Autodesk Fusion 360 part; units mm, degrees
(part 2 of 2)
sketch "Sketch127" plane through (-0.4, 0, 0) normal (1, 0, 0) x (0, 0, -1)
  line L0 (-20.3909, 26) -> (20.3909, 26)
  line L1 (20.3909, 26) -> (20.3909, 30.9997)
  line L2 (20.3909, 30.9997) -> (-20.3909, 30.9997)
  line L3 (-20.3909, 30.9997) -> (-20.3909, 26)
ref_plane "WorkPlane128" through (30.4, 0, 0) normal (1, 0, 0) x (0, 1, 0)
sketch "Sketch128" plane through (30.4, 0, 0) normal (1, 0, 0) x (0, 0, -1)
  line L0 (-20.5, 26) -> (20.5, 26)
  line L1 (20.5, 26) -> (20.5, 31)
  line L2 (20.5, 31) -> (-20.5, 31)
  line L3 (-20.5, 31) -> (-20.5, 26)
loft "Loft61" add profiles "Sketch127", "Sketch128" section 1 section 2 separate body makes body 67
ref_plane "WorkPlane129" through (29.6, 0, 0) normal (1, 0, 0) x (0, 1, 0)
sketch "Sketch129" plane through (29.6, 0, 0) normal (1, 0, 0) x (0, 0, -1)
  line L0 (-20.5, 26) -> (20.5, 26)
  line L1 (20.5, 26) -> (20.5, 31)
  line L2 (20.5, 31) -> (-20.5, 31)
  line L3 (-20.5, 31) -> (-20.5, 26)
ref_plane "WorkPlane130" through (60.4, 0, 0) normal (1, 0, 0) x (0, 1, 0)
sketch "Sketch130" plane through (60.4, 0, 0) normal (1, 0, 0) x (0, 0, -1)
  line L0 (-20.5, 26) -> (20.5, 26)
  line L1 (20.5, 26) -> (20.5, 31)
  line L2 (20.5, 31) -> (-20.5, 31)
  line L3 (-20.5, 31) -> (-20.5, 26)
loft "Loft62" add profiles "Sketch129", "Sketch130" section 1 section 2 separate body makes body 68
ref_plane "WorkPlane131" through (59.6, 0, 0) normal (1, 0, 0) x (0, 1, 0)
sketch "Sketch131" plane through (59.6, 0, 0) normal (1, 0, 0) x (0, 0, -1)
  line L0 (-20.5, 26) -> (20.5, 26)
  line L1 (20.5, 26) -> (20.5, 31)
  line L2 (20.5, 31) -> (-20.5, 31)
  line L3 (-20.5, 31) -> (-20.5, 26)
ref_plane "WorkPlane132" through (90.4, 0, 0) normal (1, 0, 0) x (0, 1, 0)
sketch "Sketch132" plane through (90.4, 0, 0) normal (1, 0, 0) x (0, 0, -1)
  line L0 (-20.5, 26) -> (20.5, 26)
  line L1 (20.5, 26) -> (20.5, 31)
  line L2 (20.5, 31) -> (-20.5, 31)
  line L3 (-20.5, 31) -> (-20.5, 26)
loft "Loft63" add profiles "Sketch131", "Sketch132" section 1 section 2 separate body makes body 69
ref_plane "WorkPlane133" through (89.6, 0, 0) normal (1, 0, 0) x (0, 1, 0)
sketch "Sketch133" plane through (89.6, 0, 0) normal (1, 0, 0) x (0, 0, -1)
  line L0 (-20.5, 26) -> (20.5, 26)
  line L1 (20.5, 26) -> (20.5, 31)
  line L2 (20.5, 31) -> (-20.5, 31)
  line L3 (-20.5, 31) -> (-20.5, 26)
ref_plane "WorkPlane134" through (120.4, 0, 0) normal (1, 0, 0) x (0, 1, 0)
sketch "Sketch134" plane through (120.4, 0, 0) normal (1, 0, 0) x (0, 0, -1)
  line L0 (-20.5, 26) -> (20.5, 26)
  line L1 (20.5, 26) -> (20.5, 30.9848)
  line L2 (20.5, 30.9848) -> (-20.5, 30.9848)
  line L3 (-20.5, 30.9848) -> (-20.5, 26)
loft "Loft64" add profiles "Sketch133", "Sketch134" section 1 section 2 separate body makes body 70
ref_plane "WorkPlane135" through (119.6, 0, 0) normal (1, 0, 0) x (0, 1, 0)
sketch "Sketch135" plane through (119.6, 0, 0) normal (1, 0, 0) x (0, 0, -1)
  line L0 (-20.5, 26) -> (20.5, 26)
  line L1 (20.5, 26) -> (20.5, 31)
  line L2 (20.5, 31) -> (-20.5, 31)
  line L3 (-20.5, 31) -> (-20.5, 26)
ref_plane "WorkPlane136" through (122.4, 0, 0) normal (1, 0, 0) x (0, 1, 0)
sketch "Sketch136" plane through (122.4, 0, 0) normal (1, 0, 0) x (0, 0, -1)
  line L0 (-20.4147, 25.9059) -> (20.4147, 25.9059)
  line L1 (20.4147, 25.9059) -> (20.4147, 30.8142)
  line L2 (20.4147, 30.8142) -> (-20.4147, 30.8142)
  line L3 (-20.4147, 30.8142) -> (-20.4147, 25.9059)
loft "Loft65" add profiles "Sketch135", "Sketch136" section 1 section 2 separate body makes body 71
ref_plane "WorkPlane137" through (121.6, 0, 0) normal (1, 0, 0) x (0, 1, 0)
sketch "Sketch137" plane through (121.6, 0, 0) normal (1, 0, 0) x (0, 0, -1)
  line L0 (-20.5, 26) -> (20.5, 26)
  line L1 (20.5, 26) -> (20.5, 30.939)
  line L2 (20.5, 30.939) -> (-20.5, 30.939)
  line L3 (-20.5, 30.939) -> (-20.5, 26)
ref_plane "WorkPlane138" through (132.0667, 0, 0) normal (1, 0, 0) x (0, 1, 0)
sketch "Sketch138" plane through (132.0667, 0, 0) normal (1, 0, 0) x (0, 0, -1)
  line L0 (-18.3534, 23.6314) -> (18.3534, 23.6314)
  line L1 (18.3534, 23.6314) -> (18.3534, 28.16)
  line L2 (18.3534, 28.16) -> (-18.3534, 28.16)
  line L3 (-18.3534, 28.16) -> (-18.3534, 23.6314)
loft "Loft66" add profiles "Sketch137", "Sketch138" section 1 section 2 separate body makes body 72
ref_plane "WorkPlane139" through (131.2667, 0, 0) normal (1, 0, 0) x (0, 1, 0)
sketch "Sketch139" plane through (131.2667, 0, 0) normal (1, 0, 0) x (0, 0, -1)
  line L0 (-18.524, 23.8196) -> (18.524, 23.8196)
  line L1 (18.524, 23.8196) -> (18.524, 28.3803)
  line L2 (18.524, 28.3803) -> (-18.524, 28.3803)
  line L3 (-18.524, 28.3803) -> (-18.524, 23.8196)
ref_plane "WorkPlane140" through (143.7333, 0, 0) normal (1, 0, 0) x (0, 1, 0)
sketch "Sketch140" plane through (143.7333, 0, 0) normal (1, 0, 0) x (0, 0, -1)
  line L0 (-15.8657, 20.8863) -> (15.8657, 20.8863)
  line L1 (15.8657, 20.8863) -> (15.8657, 24.9301)
  line L2 (15.8657, 24.9301) -> (-15.8657, 24.9301)
  line L3 (-15.8657, 24.9301) -> (-15.8657, 20.8863)
loft "Loft67" add profiles "Sketch139", "Sketch140" section 1 section 2 separate body makes body 73
ref_plane "WorkPlane141" through (142.9333, 0, 0) normal (1, 0, 0) x (0, 1, 0)
sketch "Sketch141" plane through (142.9333, 0, 0) normal (1, 0, 0) x (0, 0, -1)
  line L0 (-16.0363, 21.0745) -> (16.0363, 21.0745)
  line L1 (16.0363, 21.0745) -> (16.0363, 25.1527)
  line L2 (16.0363, 25.1527) -> (-16.0363, 25.1527)
  line L3 (-16.0363, 25.1527) -> (-16.0363, 21.0745)
ref_plane "WorkPlane142" through (155.4, 0, 0) normal (1, 0, 0) x (0, 1, 0)
sketch "Sketch142" plane through (155.4, 0, 0) normal (1, 0, 0) x (0, 0, -1)
  line L0 (-13.3779, 18.1412) -> (13.3779, 18.1412)
  line L1 (13.3779, 18.1412) -> (13.3779, 21.6616)
  line L2 (13.3779, 21.6616) -> (-13.3779, 21.6616)
  line L3 (-13.3779, 21.6616) -> (-13.3779, 18.1412)
loft "Loft68" add profiles "Sketch141", "Sketch142" section 1 section 2 separate body makes body 74
ref_plane "WorkPlane143" through (154.6, 0, 0) normal (1, 0, 0) x (0, 1, 0)
sketch "Sketch143" plane through (154.6, 0, 0) normal (1, 0, 0) x (0, 0, -1)
  line L0 (-13.5485, 18.3294) -> (13.5485, 18.3294)
  line L1 (13.5485, 18.3294) -> (13.5485, 21.8873)
  line L2 (13.5485, 21.8873) -> (-13.5485, 21.8873)
  line L3 (-13.5485, 21.8873) -> (-13.5485, 18.3294)
ref_plane "WorkPlane144" through (167.0667, 0, 0) normal (1, 0, 0) x (0, 1, 0)
sketch "Sketch144" plane through (167.0667, 0, 0) normal (1, 0, 0) x (0, 0, -1)
  line L0 (-10.8902, 15.3961) -> (10.8902, 15.3961)
  line L1 (10.8902, 15.3961) -> (10.8902, 18.336)
  line L2 (10.8902, 18.336) -> (-10.8902, 18.336)
  line L3 (-10.8902, 18.336) -> (-10.8902, 15.3961)
loft "Loft69" add profiles "Sketch143", "Sketch144" section 1 section 2 separate body makes body 75
ref_plane "WorkPlane145" through (166.2667, 0, 0) normal (1, 0, 0) x (0, 1, 0)
sketch "Sketch145" plane through (166.2667, 0, 0) normal (1, 0, 0) x (0, 0, -1)
  line L0 (-11.0608, 15.5843) -> (11.0608, 15.5843)
  line L1 (11.0608, 15.5843) -> (11.0608, 18.5666)
  line L2 (11.0608, 18.5666) -> (-11.0608, 18.5666)
  line L3 (-11.0608, 18.5666) -> (-11.0608, 15.5843)
ref_plane "WorkPlane146" through (178.7333, 0, 0) normal (1, 0, 0) x (0, 1, 0)
sketch "Sketch146" plane through (178.7333, 0, 0) normal (1, 0, 0) x (0, 0, -1)
  line L0 (-8.4025, 12.651) -> (8.4025, 12.651)
  line L1 (8.4025, 12.651) -> (8.4025, 14.9089)
  line L2 (8.4025, 14.9089) -> (-8.4025, 14.9089)
  line L3 (-8.4025, 14.9089) -> (-8.4025, 12.651)
loft "Loft70" add profiles "Sketch145", "Sketch146" section 1 section 2 separate body makes body 76
ref_plane "WorkPlane147" through (177.9333, 0, 0) normal (1, 0, 0) x (0, 1, 0)
sketch "Sketch147" plane through (177.9333, 0, 0) normal (1, 0, 0) x (0, 0, -1)
  line L0 (-8.573, 12.8392) -> (8.573, 12.8392)
  line L1 (8.573, 12.8392) -> (8.573, 15.1492)
  line L2 (8.573, 15.1492) -> (-8.573, 15.1492)
  line L3 (-8.573, 15.1492) -> (-8.573, 12.8392)
ref_plane "WorkPlane148" through (190, 0, 0) normal (1, 0, 0) x (0, 1, 0)
sketch "Sketch148" plane through (190, 0, 0) normal (1, 0, 0) x (0, 0, -1)
  line L0 (-6, 10) -> (6, 10)
  line L1 (6, 10) -> (6, 11.2)
  line L2 (6, 11.2) -> (-6, 11.2)
  line L3 (-6, 11.2) -> (-6, 10)
loft "Loft71" add profiles "Sketch147", "Sketch148" section 1 section 2 separate body makes body 77
ref_plane "WorkPlane149" through (-30, 0, 0) normal (1, 0, 0) x (0, 1, 0)
sketch "Sketch149" plane through (-30, 0, 0) normal (1, 0, 0) x (0, 0, -1)
  line L0 (-11, -25.2) -> (11, -25.2)
  line L1 (11, -25.2) -> (11, -24)
  line L2 (11, -24) -> (-11, -24)
  line L3 (-11, -24) -> (-11, -25.2)
ref_plane "WorkPlane150" through (-23.6, 0, 0) normal (1, 0, 0) x (0, 1, 0)
sketch "Sketch150" plane through (-23.6, 0, 0) normal (1, 0, 0) x (0, 0, -1)
  line L0 (-13.8, -29.146) -> (13.8, -29.146)
  line L1 (13.8, -29.146) -> (13.8, -25.6)
  line L2 (13.8, -25.6) -> (-13.8, -25.6)
  line L3 (-13.8, -25.6) -> (-13.8, -29.146)
loft "Loft72" add profiles "Sketch149", "Sketch150" section 1 section 2 separate body makes body 78
ref_plane "WorkPlane151" through (-24.4, 0, 0) normal (1, 0, 0) x (0, 1, 0)
sketch "Sketch151" plane through (-24.4, 0, 0) normal (1, 0, 0) x (0, 0, -1)
  line L0 (-13.45, -28.8108) -> (13.45, -28.8108)
  line L1 (13.45, -28.8108) -> (13.45, -25.4)
  line L2 (13.45, -25.4) -> (-13.45, -25.4)
  line L3 (-13.45, -25.4) -> (-13.45, -28.8108)
ref_plane "WorkPlane152" through (-21.6, 0, 0) normal (1, 0, 0) x (0, 1, 0)
sketch "Sketch152" plane through (-21.6, 0, 0) normal (1, 0, 0) x (0, 0, -1)
  line L0 (-14.6091, -29.8371) -> (14.6091, -29.8371)
  line L1 (14.6091, -29.8371) -> (14.6091, -26)
  line L2 (14.6091, -26) -> (-14.6091, -26)
  line L3 (-14.6091, -26) -> (-14.6091, -29.8371)
loft "Loft73" add profiles "Sketch151", "Sketch152" section 1 section 2 separate body makes body 79
ref_plane "WorkPlane153" through (-22.4, 0, 0) normal (1, 0, 0) x (0, 1, 0)
sketch "Sketch153" plane through (-22.4, 0, 0) normal (1, 0, 0) x (0, 0, -1)
  line L0 (-14.325, -29.6278) -> (14.325, -29.6278)
  line L1 (14.325, -29.6278) -> (14.325, -25.9)
  line L2 (14.325, -25.9) -> (-14.325, -25.9)
  line L3 (-14.325, -25.9) -> (-14.325, -29.6278)
ref_plane "WorkPlane154" through (-17.6, 0, 0) normal (1, 0, 0) x (0, 1, 0)
sketch "Sketch154" plane through (-17.6, 0, 0) normal (1, 0, 0) x (0, 0, -1)
  line L0 (-15.7, -30.2773) -> (15.7, -30.2773)
  line L1 (15.7, -30.2773) -> (15.7, -26)
  line L2 (15.7, -26) -> (-15.7, -26)
  line L3 (-15.7, -26) -> (-15.7, -30.2773)
loft "Loft74" add profiles "Sketch153", "Sketch154" section 1 section 2 separate body makes body 80
ref_plane "WorkPlane155" through (-18.4, 0, 0) normal (1, 0, 0) x (0, 1, 0)
sketch "Sketch155" plane through (-18.4, 0, 0) normal (1, 0, 0) x (0, 0, -1)
  line L0 (-15.4818, -30.2013) -> (15.4818, -30.2013)
  line L1 (15.4818, -30.2013) -> (15.4818, -26)
  line L2 (15.4818, -26) -> (-15.4818, -26)
  line L3 (-15.4818, -26) -> (-15.4818, -30.2013)
ref_plane "WorkPlane156" through (-11.6, 0, 0) normal (1, 0, 0) x (0, 1, 0)
sketch "Sketch156" plane through (-11.6, 0, 0) normal (1, 0, 0) x (0, 0, -1)
  line L0 (-17.3364, -30.7044) -> (17.3364, -30.7044)
  line L1 (17.3364, -30.7044) -> (17.3364, -26)
  line L2 (17.3364, -26) -> (-17.3364, -26)
  line L3 (-17.3364, -26) -> (-17.3364, -30.7044)
loft "Loft75" add profiles "Sketch155", "Sketch156" section 1 section 2 separate body makes body 81
ref_plane "WorkPlane157" through (-12.4, 0, 0) normal (1, 0, 0) x (0, 1, 0)
sketch "Sketch157" plane through (-12.4, 0, 0) normal (1, 0, 0) x (0, 0, -1)
  line L0 (-17.1182, -30.6602) -> (17.1182, -30.6602)
  line L1 (17.1182, -30.6602) -> (17.1182, -26)
  line L2 (17.1182, -26) -> (-17.1182, -26)
  line L3 (-17.1182, -26) -> (-17.1182, -30.6602)
ref_plane "WorkPlane158" through (-5.6, 0, 0) normal (1, 0, 0) x (0, 1, 0)
sketch "Sketch158" plane through (-5.6, 0, 0) normal (1, 0, 0) x (0, 0, -1)
  line L0 (-18.9727, -30.9332) -> (18.9727, -30.9332)
  line L1 (18.9727, -30.9332) -> (18.9727, -26)
  line L2 (18.9727, -26) -> (-18.9727, -26)
  line L3 (-18.9727, -26) -> (-18.9727, -30.9332)
loft "Loft76" add profiles "Sketch157", "Sketch158" section 1 section 2 separate body makes body 82
ref_plane "WorkPlane159" through (-6.4, 0, 0) normal (1, 0, 0) x (0, 1, 0)
sketch "Sketch159" plane through (-6.4, 0, 0) normal (1, 0, 0) x (0, 0, -1)
  line L0 (-18.7545, -30.9125) -> (18.7545, -30.9125)
  line L1 (18.7545, -30.9125) -> (18.7545, -26)
  line L2 (18.7545, -26) -> (-18.7545, -26)
  line L3 (-18.7545, -26) -> (-18.7545, -30.9125)
ref_plane "WorkPlane160" through (0.4, 0, 0) normal (1, 0, 0) x (0, 1, 0)
sketch "Sketch160" plane through (0.4, 0, 0) normal (1, 0, 0) x (0, 0, -1)
  line L0 (-20.5, -31) -> (20.5, -31)
  line L1 (20.5, -31) -> (20.5, -26)
  line L2 (20.5, -26) -> (-20.5, -26)
  line L3 (-20.5, -26) -> (-20.5, -31)
loft "Loft77" add profiles "Sketch159", "Sketch160" section 1 section 2 separate body makes body 83
ref_plane "WorkPlane161" through (-0.4, 0, 0) normal (1, 0, 0) x (0, 1, 0)
sketch "Sketch161" plane through (-0.4, 0, 0) normal (1, 0, 0) x (0, 0, -1)
  line L0 (-20.3909, -30.9997) -> (20.3909, -30.9997)
  line L1 (20.3909, -30.9997) -> (20.3909, -26)
  line L2 (20.3909, -26) -> (-20.3909, -26)
  line L3 (-20.3909, -26) -> (-20.3909, -30.9997)
ref_plane "WorkPlane162" through (30.4, 0, 0) normal (1, 0, 0) x (0, 1, 0)
sketch "Sketch162" plane through (30.4, 0, 0) normal (1, 0, 0) x (0, 0, -1)
  line L0 (-20.5, -31) -> (20.5, -31)
  line L1 (20.5, -31) -> (20.5, -26)
  line L2 (20.5, -26) -> (-20.5, -26)
  line L3 (-20.5, -26) -> (-20.5, -31)
loft "Loft78" add profiles "Sketch161", "Sketch162" section 1 section 2 separate body makes body 84
ref_plane "WorkPlane163" through (29.6, 0, 0) normal (1, 0, 0) x (0, 1, 0)
sketch "Sketch163" plane through (29.6, 0, 0) normal (1, 0, 0) x (0, 0, -1)
  line L0 (-20.5, -31) -> (20.5, -31)
  line L1 (20.5, -31) -> (20.5, -26)
  line L2 (20.5, -26) -> (-20.5, -26)
  line L3 (-20.5, -26) -> (-20.5, -31)
ref_plane "WorkPlane164" through (60.4, 0, 0) normal (1, 0, 0) x (0, 1, 0)
sketch "Sketch164" plane through (60.4, 0, 0) normal (1, 0, 0) x (0, 0, -1)
  line L0 (-20.5, -31) -> (20.5, -31)
  line L1 (20.5, -31) -> (20.5, -26)
  line L2 (20.5, -26) -> (-20.5, -26)
  line L3 (-20.5, -26) -> (-20.5, -31)
loft "Loft79" add profiles "Sketch163", "Sketch164" section 1 section 2 separate body makes body 85
ref_plane "WorkPlane165" through (59.6, 0, 0) normal (1, 0, 0) x (0, 1, 0)
sketch "Sketch165" plane through (59.6, 0, 0) normal (1, 0, 0) x (0, 0, -1)
  line L0 (-20.5, -31) -> (20.5, -31)
  line L1 (20.5, -31) -> (20.5, -26)
  line L2 (20.5, -26) -> (-20.5, -26)
  line L3 (-20.5, -26) -> (-20.5, -31)
ref_plane "WorkPlane166" through (90.4, 0, 0) normal (1, 0, 0) x (0, 1, 0)
sketch "Sketch166" plane through (90.4, 0, 0) normal (1, 0, 0) x (0, 0, -1)
  line L0 (-20.5, -31) -> (20.5, -31)
  line L1 (20.5, -31) -> (20.5, -26)
  line L2 (20.5, -26) -> (-20.5, -26)
  line L3 (-20.5, -26) -> (-20.5, -31)
loft "Loft80" add profiles "Sketch165", "Sketch166" section 1 section 2 separate body makes body 86
ref_plane "WorkPlane167" through (89.6, 0, 0) normal (1, 0, 0) x (0, 1, 0)
sketch "Sketch167" plane through (89.6, 0, 0) normal (1, 0, 0) x (0, 0, -1)
  line L0 (-20.5, -31) -> (20.5, -31)
  line L1 (20.5, -31) -> (20.5, -26)
  line L2 (20.5, -26) -> (-20.5, -26)
  line L3 (-20.5, -26) -> (-20.5, -31)
ref_plane "WorkPlane168" through (120.4, 0, 0) normal (1, 0, 0) x (0, 1, 0)
sketch "Sketch168" plane through (120.4, 0, 0) normal (1, 0, 0) x (0, 0, -1)
  line L0 (-20.5, -30.9848) -> (20.5, -30.9848)
  line L1 (20.5, -30.9848) -> (20.5, -26)
  line L2 (20.5, -26) -> (-20.5, -26)
  line L3 (-20.5, -26) -> (-20.5, -30.9848)
loft "Loft81" add profiles "Sketch167", "Sketch168" section 1 section 2 separate body makes body 87
ref_plane "WorkPlane169" through (119.6, 0, 0) normal (1, 0, 0) x (0, 1, 0)
sketch "Sketch169" plane through (119.6, 0, 0) normal (1, 0, 0) x (0, 0, -1)
  line L0 (-20.5, -31) -> (20.5, -31)
  line L1 (20.5, -31) -> (20.5, -26)
  line L2 (20.5, -26) -> (-20.5, -26)
  line L3 (-20.5, -26) -> (-20.5, -31)
ref_plane "WorkPlane170" through (122.4, 0, 0) normal (1, 0, 0) x (0, 1, 0)
sketch "Sketch170" plane through (122.4, 0, 0) normal (1, 0, 0) x (0, 0, -1)
  line L0 (-20.4147, -30.8142) -> (20.4147, -30.8142)
  line L1 (20.4147, -30.8142) -> (20.4147, -25.9059)
  line L2 (20.4147, -25.9059) -> (-20.4147, -25.9059)
  line L3 (-20.4147, -25.9059) -> (-20.4147, -30.8142)
loft "Loft82" add profiles "Sketch169", "Sketch170" section 1 section 2 separate body makes body 88
ref_plane "WorkPlane171" through (121.6, 0, 0) normal (1, 0, 0) x (0, 1, 0)
sketch "Sketch171" plane through (121.6, 0, 0) normal (1, 0, 0) x (0, 0, -1)
  line L0 (-20.5, -30.939) -> (20.5, -30.939)
  line L1 (20.5, -30.939) -> (20.5, -26)
  line L2 (20.5, -26) -> (-20.5, -26)
  line L3 (-20.5, -26) -> (-20.5, -30.939)
ref_plane "WorkPlane172" through (132.0667, 0, 0) normal (1, 0, 0) x (0, 1, 0)
sketch "Sketch172" plane through (132.0667, 0, 0) normal (1, 0, 0) x (0, 0, -1)
  line L0 (-18.3534, -28.16) -> (18.3534, -28.16)
  line L1 (18.3534, -28.16) -> (18.3534, -23.6314)
  line L2 (18.3534, -23.6314) -> (-18.3534, -23.6314)
  line L3 (-18.3534, -23.6314) -> (-18.3534, -28.16)
loft "Loft83" add profiles "Sketch171", "Sketch172" section 1 section 2 separate body makes body 89
ref_plane "WorkPlane173" through (131.2667, 0, 0) normal (1, 0, 0) x (0, 1, 0)
sketch "Sketch173" plane through (131.2667, 0, 0) normal (1, 0, 0) x (0, 0, -1)
  line L0 (-18.524, -28.3803) -> (18.524, -28.3803)
  line L1 (18.524, -28.3803) -> (18.524, -23.8196)
  line L2 (18.524, -23.8196) -> (-18.524, -23.8196)
  line L3 (-18.524, -23.8196) -> (-18.524, -28.3803)
ref_plane "WorkPlane174" through (143.7333, 0, 0) normal (1, 0, 0) x (0, 1, 0)
sketch "Sketch174" plane through (143.7333, 0, 0) normal (1, 0, 0) x (0, 0, -1)
  line L0 (-15.8657, -24.9301) -> (15.8657, -24.9301)
  line L1 (15.8657, -24.9301) -> (15.8657, -20.8863)
  line L2 (15.8657, -20.8863) -> (-15.8657, -20.8863)
  line L3 (-15.8657, -20.8863) -> (-15.8657, -24.9301)
loft "Loft84" add profiles "Sketch173", "Sketch174" section 1 section 2 separate body makes body 90
ref_plane "WorkPlane175" through (142.9333, 0, 0) normal (1, 0, 0) x (0, 1, 0)
sketch "Sketch175" plane through (142.9333, 0, 0) normal (1, 0, 0) x (0, 0, -1)
  line L0 (-16.0363, -25.1527) -> (16.0363, -25.1527)
  line L1 (16.0363, -25.1527) -> (16.0363, -21.0745)
  line L2 (16.0363, -21.0745) -> (-16.0363, -21.0745)
  line L3 (-16.0363, -21.0745) -> (-16.0363, -25.1527)
ref_plane "WorkPlane176" through (155.4, 0, 0) normal (1, 0, 0) x (0, 1, 0)
sketch "Sketch176" plane through (155.4, 0, 0) normal (1, 0, 0) x (0, 0, -1)
  line L0 (-13.3779, -21.6616) -> (13.3779, -21.6616)
  line L1 (13.3779, -21.6616) -> (13.3779, -18.1412)
  line L2 (13.3779, -18.1412) -> (-13.3779, -18.1412)
  line L3 (-13.3779, -18.1412) -> (-13.3779, -21.6616)
loft "Loft85" add profiles "Sketch175", "Sketch176" section 1 section 2 separate body makes body 91
ref_plane "WorkPlane177" through (154.6, 0, 0) normal (1, 0, 0) x (0, 1, 0)
sketch "Sketch177" plane through (154.6, 0, 0) normal (1, 0, 0) x (0, 0, -1)
  line L0 (-13.5485, -21.8873) -> (13.5485, -21.8873)
  line L1 (13.5485, -21.8873) -> (13.5485, -18.3294)
  line L2 (13.5485, -18.3294) -> (-13.5485, -18.3294)
  line L3 (-13.5485, -18.3294) -> (-13.5485, -21.8873)
ref_plane "WorkPlane178" through (167.0667, 0, 0) normal (1, 0, 0) x (0, 1, 0)
sketch "Sketch178" plane through (167.0667, 0, 0) normal (1, 0, 0) x (0, 0, -1)
  line L0 (-10.8902, -18.336) -> (10.8902, -18.336)
  line L1 (10.8902, -18.336) -> (10.8902, -15.3961)
  line L2 (10.8902, -15.3961) -> (-10.8902, -15.3961)
  line L3 (-10.8902, -15.3961) -> (-10.8902, -18.336)
loft "Loft86" add profiles "Sketch177", "Sketch178" section 1 section 2 separate body makes body 92
ref_plane "WorkPlane179" through (166.2667, 0, 0) normal (1, 0, 0) x (0, 1, 0)
sketch "Sketch179" plane through (166.2667, 0, 0) normal (1, 0, 0) x (0, 0, -1)
  line L0 (-11.0608, -18.5666) -> (11.0608, -18.5666)
  line L1 (11.0608, -18.5666) -> (11.0608, -15.5843)
  line L2 (11.0608, -15.5843) -> (-11.0608, -15.5843)
  line L3 (-11.0608, -15.5843) -> (-11.0608, -18.5666)
ref_plane "WorkPlane180" through (178.7333, 0, 0) normal (1, 0, 0) x (0, 1, 0)
sketch "Sketch180" plane through (178.7333, 0, 0) normal (1, 0, 0) x (0, 0, -1)
  line L0 (-8.4025, -14.9089) -> (8.4025, -14.9089)
  line L1 (8.4025, -14.9089) -> (8.4025, -12.651)
  line L2 (8.4025, -12.651) -> (-8.4025, -12.651)
  line L3 (-8.4025, -12.651) -> (-8.4025, -14.9089)
loft "Loft87" add profiles "Sketch179", "Sketch180" section 1 section 2 separate body makes body 93
ref_plane "WorkPlane181" through (177.9333, 0, 0) normal (1, 0, 0) x (0, 1, 0)
sketch "Sketch181" plane through (177.9333, 0, 0) normal (1, 0, 0) x (0, 0, -1)
  line L0 (-8.573, -15.1492) -> (8.573, -15.1492)
  line L1 (8.573, -15.1492) -> (8.573, -12.8392)
  line L2 (8.573, -12.8392) -> (-8.573, -12.8392)
  line L3 (-8.573, -12.8392) -> (-8.573, -15.1492)
ref_plane "WorkPlane182" through (190, 0, 0) normal (1, 0, 0) x (0, 1, 0)
sketch "Sketch182" plane through (190, 0, 0) normal (1, 0, 0) x (0, 0, -1)
  line L0 (-6, -11.2) -> (6, -11.2)
  line L1 (6, -11.2) -> (6, -10)
  line L2 (6, -10) -> (-6, -10)
  line L3 (-6, -10) -> (-6, -11.2)
loft "Loft88" add profiles "Sketch181", "Sketch182" section 1 section 2 separate body makes body 94
ref_plane "WorkPlane183" through (-28, 0, 0) normal (1, 0, 0) x (0, 1, 0)
sketch "fair_nose_bulkhead" plane through (-28, 0, 0) normal (1, 0, 0) x (0, 0, -1)
  line L0 (-11.875, -24.5) -> (11.875, -24.5)
  line L1 (11.875, -24.5) -> (11.875, 24.5)
  line L2 (11.875, 24.5) -> (-11.875, 24.5)
  line L3 (-11.875, 24.5) -> (-11.875, -24.5)
  line L4 (-10.5, -23.5) -> (10.5, -23.5)
  line L5 (10.5, -23.5) -> (10.5, 23.5)
  line L6 (10.5, 23.5) -> (-10.5, 23.5)
  line L7 (-10.5, 23.5) -> (-10.5, -23.5)
extrude "Extrude7" add sketch "fair_nose_bulkhead" along normal mid plane 2 separate body makes body 95
ref_plane "WorkPlane184" through (189, 0, 0) normal (1, 0, 0) x (0, 1, 0)
sketch "fair_tail_bulkhead" plane through (189, 0, 0) normal (1, 0, 0) x (0, 0, -1)
  line L0 (-6.2132, -10.2353) -> (6.2132, -10.2353)
  line L1 (6.2132, -10.2353) -> (6.2132, 10.2353)
  line L2 (6.2132, 10.2353) -> (-6.2132, 10.2353)
  line L3 (-6.2132, 10.2353) -> (-6.2132, -10.2353)
extrude "Extrude8" add sketch "fair_tail_bulkhead" along normal mid plane 2 separate body makes body 96
named bodies: "plate_a", "plate_b", "rail_left", "rail_right", "bm_top_s00", "bm_top_s01", "bm_top_s02", "bm_top_s03", "bm_top_s04", "bm_bottom_s00", "bm_bottom_s01", "bm_bottom_s02", "bm_bottom_s03", "bm_bottom_s04", "bm_left_s00", "bm_left_s01", "bm_left_s02", "bm_left_s03", "bm_left_s04", "bm_right_s00", "bm_right_s01", "bm_right_s02", "bm_right_s03", "bm_right_s04", "front_flange", "rear_cap", "f_top_s00", "f_top_s01", "f_top_s02", "f_top_s03", "f_top_s04", "f_top_s05", "f_top_s06", "f_top_s07", "f_top_s08", "f_top_s09", "f_top_s10", "f_top_s11", "f_top_s12", "f_top_s13", "f_top_s14", "f_top_s15", "f_top_s16", "f_bottom_s00", "f_bottom_s01", "f_bottom_s02", "f_bottom_s03", "f_bottom_s04", "f_bottom_s05", "f_bottom_s06", "f_bottom_s07", "f_bottom_s08", "f_bottom_s09", "f_bottom_s10", "f_bottom_s11", "f_bottom_s12", "f_bottom_s13", "f_bottom_s14", "f_bottom_s15", "f_bottom_s16", "f_right_s00", "f_right_s01", "f_right_s02", "f_right_s03", "f_right_s04", "f_right_s05", "f_right_s06", "f_right_s07", "f_right_s08", "f_right_s09", "f_right_s10", "f_right_s11", "f_right_s12", "f_right_s13", "f_right_s14", "f_right_s15", "f_right_s16", "f_left_s00", "f_left_s01", "f_left_s02", "f_left_s03", "f_left_s04", "f_left_s05", "f_left_s06", "f_left_s07", "f_left_s08", "f_left_s09", "f_left_s10", "f_left_s11", "f_left_s12", "f_left_s13", "f_left_s14", "f_left_s15", "f_left_s16", "fair_nose_bulkhead", "fair_tail_bulkhead"
